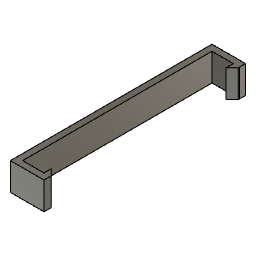
water_level_sensor_clip_2024-10-06 (Autodesk Fusion 360 design; units mm, degrees)
Autodesk Fusion 360 part; units mm, degrees
sketch "스케치1" plane through (0, 0, 0) normal (0, 0, 1) x (1, 0, 0)
sketch "스케치2" plane through (0, 0, 0) normal (0, 0, 1) x (1, 0, 0)
sketch "스케치3" plane through (0, 0, 0) normal (0, 0, 1) x (1, 0, 0)
sketch "스케치4" plane through (0, 0, 0) normal (0, 0, 1) x (1, 0, 0)
sketch "스케치5" plane through (0, 0, 0) normal (0, 0, 1) x (1, 0, 0)
  line L0 (0, 0) -> (7, 0)
  line L1 (37.6739, 0) -> (37.6739, -1)
  line L2 (0, 62) -> (0, 0)
  line L3 (0, 62) -> (7, 62)
  line L4 (-2, 64) -> (-2, -2)
  line L5 (-2, 64) -> (11.4142, 64)
  line L6 (-2, -2) -> (11.4142, -2)
  line L7 (7, 59.5858) -> (11.4142, 64)
  line L8 (7, 2.4142) -> (11.4142, -2)
  line L9 (7, 62) -> (7, 59.5858)
  line L10 (7, 2.4142) -> (7, 0)
  constraint horizontal L0
  constraint perpendicular L0 L1
  constraint vertical L2
  constraint horizontal L3
  constraint coincident L0 L2.end
  constraint vertical L9
  constraint vertical L4
  constraint horizontal L5
  constraint horizontal L6
  constraint coincident L2 L0.start
  constraint coincident L8.start L9
  constraint collinear L9 L10
extrude "돌출1" add sketch "스케치5" along normal blind 9
move_face "면 간격띄우기1" offset -0.5 1 faces at (7, 61.1953, 3)
sketch "스케치6" plane through (0, 0, 9) normal (0, 0, 1) x (-1, 0, 0)
  line L0 (2, -64) -> (2, 2)
  line L1 (2, 2) -> (-11.4142, 2)
  line L2 (-11.4142, 2) -> (-7, -2.4142)
  line L3 (-7, -2.4142) -> (-7, 0)
  line L4 (-7, 0) -> (0, 0)
  line L5 (0, 0) -> (0, -62)
  line L6 (0, -62) -> (-7.5, -62)
  line L7 (-7.5, -62) -> (-7.5, -60.0858)
  line L8 (-7.5, -60.0858) -> (-11.4142, -64)
  line L9 (-11.4142, -64) -> (2, -64)
  line L10 (-7, 0) -> (-7, -2.4142)
  line L11 (-7.5, 0) -> (-7.5, -4.7916)
  line L12 (-7, -2.4142) -> (-7.5, -4.7916)
  line L13 (-7, 0) -> (-7.5, 0)
  constraint coincident L3.end L4.start
  constraint coincident L2.end L3.start
  constraint parallel L4 L13
extrude "돌출2" cut sketch "스케치6" against normal blind 9.5 contours L2 L11 L12
sketch "스케치7" plane through (0, 0, 9) normal (0, 0, 1) x (-1, 0, 0)
  line L0 (-7, 0) -> (0, 0)
  line L1 (0, 0) -> (0, -62)
  line L2 (0, -62) -> (-7.5, -62)
  line L3 (-7.5, -62) -> (-7.5, -60.0858)
  line L4 (-7.5, -60.0858) -> (-11.4142, -64)
  line L5 (-11.4142, -64) -> (2, -64)
  line L6 (2, -64) -> (2, 2)
  line L7 (2, 2) -> (-11.4142, 2)
  line L8 (-11.4142, 2) -> (-7, -2.4142)
  line L9 (2, 15) -> (1, 15)
  line L10 (-9, -0.4142) -> (-9, 2)
  line L11 (-9, -0.4142) -> (-11.4142, 2)
  line L12 (-7, -2.4142) -> (-7, 0)
  constraint perpendicular L6 L9
  constraint coincident L8 L10.start
  constraint coincident L7.end L8.start
  constraint coincident L7 L10.end
sketch "스케치8" plane through (0, 0, 9) normal (0, 0, 1) x (-1, 0, 0)
sketch "스케치9" plane through (0, 0, 9) normal (0, 0, 1) x (-1, 0, 0)
extrude "돌출3" cut sketch "스케치7" against normal blind 11 contours L7 L8 L10 L11
sketch "스케치10" plane through (0, 0, 9) normal (0, 0, 1) x (-1, 0, 0)
  line L0 (-9, 2) -> (-9, -0.4142)
  line L1 (-9, -0.4142) -> (-7, -2.4142)
  line L2 (-7, -2.4142) -> (-7, 0)
  line L3 (-7, 0) -> (0, 0)
  line L4 (0, 0) -> (0, -62)
  line L5 (0, -62) -> (-7.5, -62)
  line L6 (-7.5, -62) -> (-7.5, -60.0858)
  line L7 (-7.5, -60.0858) -> (-11.4142, -64)
  line L8 (-11.4142, -64) -> (2, -64)
  line L9 (2, -64) -> (2, 2)
  line L10 (2, 2) -> (-9, 2)
  line L11 (2, -64) -> (2, -76)
  line L12 (-9, -61.5858) -> (-9, -64)
  line L13 (-9, -64) -> (-11.4142, -64)
  constraint coincident L8.end L9.start
  constraint perpendicular L8 L11
  constraint coincident L7 L12.start
  constraint coincident L8 L12.end
  constraint coincident L7.end L8.start
extrude "돌출4" cut sketch "스케치10" against normal blind 9 contours L7 L8 L12 L13
sketch "스케치11" plane through (0, 0, 9) normal (0, 0, 1) x (-1, 0, 0)
  line L0 (-9, -61.5858) -> (-9, -64)
  line L1 (-9, -64) -> (2, -64)
  line L2 (2, -64) -> (2, 2)
  line L3 (2, 2) -> (-9, 2)
  line L4 (-9, 2) -> (-9, -0.4142)
  line L5 (-9, -0.4142) -> (-7, -2.4142)
  line L6 (-7, -2.4142) -> (-7, 0)
  line L7 (-7, 0) -> (0, 0)
  line L8 (0, 0) -> (0, -62)
  line L9 (0, -62) -> (-7.5, -62)
  line L10 (-7.5, -60.0858) -> (-9, -61.5858)
delete_face "면 삭제1" 1 faces at (7.5, 60.7239, 6)
sketch "스케치12" plane through (0, 0, 9) normal (0, 0, 1) x (-1, 0, 0)
  line L0 (0, -62) -> (-9, -62)
  line L1 (-9, -62) -> (-9, -64)
  line L2 (-9, -64) -> (2, -64)
  line L3 (2, -64) -> (2, 2)
  line L4 (2, 2) -> (-9, 2)
  line L5 (-9, 2) -> (-9, -0.4142)
  line L6 (-9, -0.4142) -> (-7, -2.4142)
  line L7 (-7, -2.4142) -> (-7, 0)
  line L8 (-7, 0) -> (0, 0)
  line L9 (0, 0) -> (0, -62)
  line L10 (-9, -62) -> (-9, -61.586)
  line L11 (-7, -62) -> (-7, -59.586)
  line L12 (-7, -59.586) -> (-9, -61.586)
  line L13 (-7, -62) -> (-9, -62)
  constraint coincident L0 L11.start
  constraint perpendicular L0 L11
  constraint coincident L0.end L1.start
sketch "스케치13" plane through (0, 0, 9) normal (0, 0, 1) x (-1, 0, 0)
  line L0 (0, -62) -> (-9, -62)
  line L1 (-9, -62) -> (-9, -64)
  line L2 (-9, -64) -> (2, -64)
  line L3 (2, -64) -> (2, 2)
  line L4 (2, 2) -> (-9, 2)
  line L5 (-9, 2) -> (-9, -0.4142)
  line L6 (-9, -0.4142) -> (-7, -2.4142)
  line L7 (-7, -2.4142) -> (-7, 0)
  line L8 (-7, 0) -> (0, 0)
  line L9 (0, 0) -> (0, -62)
sketch "스케치14" plane through (0, 0, 0) normal (0, 0, 1) x (1, 0, 0)
extrude "돌출5" add sketch "스케치12" against normal blind 9 contours L0 L10 L11 L12 L13
